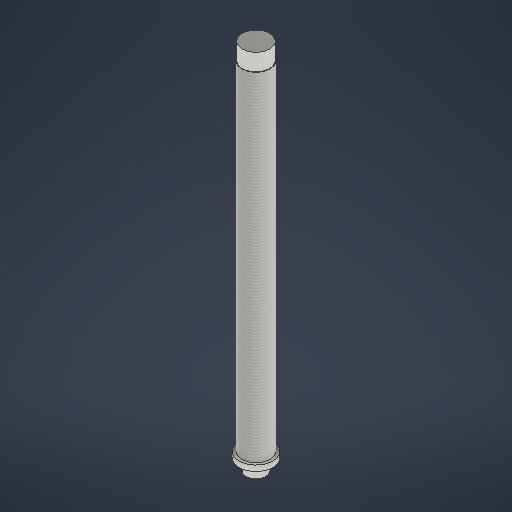
# Autodesk Inventor part: sroba_toczna
Saved by Autodesk Inventor 2027.1 (Build 311270010, 270A)
## iProperties
Created: 2026-11-04
Part Number: sroba_toczna
Material: Ogólny
Document SubType Name: Modeling
Designer: User
Density: 1 g/cm^3
Appearance: Domyślna
Author: User
Autodesk Inventor part; units mm, degrees
ref_plane "YZ Plane" through (0, 0, 0) normal (1, 0, 0) x (0, 1, 0)
ref_plane "XZ Plane" through (0, 0, 0) normal (0, 1, 0) x (-1, 0, 0)
ref_plane "XY Plane" through (0, 0, 0) normal (0, 0, 1) x (1, 0, 0)
sketch "Szkic1" plane through (0, 0, 0) normal (0, 1, 0) x (-1, 0, 0)
  circle A0 centre (0, 0) radius 5
  dimension "d0" = 10
  constraints: 1 centre point, 1 coincident
  measures "d0" diameter of A0
extrude "Wyciągnięcie proste1" add sketch "Szkic1" along normal blind 120
thread "Gwint1" size "M10x1" class "6g" standard "ANSI Metric M Profile" full length
sketch "Szkic2" plane through (0, 120, 0) normal (0, 1, 0) x (1, 0, 0)
  circle A0 centre (0, 0) radius 11.2
  circle A1 centre (0, 0) radius 4.85
  dimension "d5" = 22.4
  dimension "d6" = 9.7
  constraints: 2 centre point, 2 coincident
  measures "d5" diameter of A0
  measures "d6" diameter of A1
extrude "Wyciągnięcie proste2" add sketch "Szkic2" along normal blind 6 contours A1
sketch "Szkic3" plane through (0, 0, 0) normal (0, -1, 0) x (1, 0, 0)
  circle A0 centre (0, 0) radius 3
  line L0 (-2, 1.5) -> (2, 1.5)
  arc A1 (-2, 1.5) -> (-2, -1.5) centre (0, 0) ccw
  line L1 (2, -1.5) -> (-2, -1.5)
  arc A2 (2, -1.5) -> (2, 1.5) centre (0, 0) ccw
  arc A3 (2, 1.5) -> (-2, 1.5) centre (0, 0) ccw
  arc A4 (2, 1.5) -> (-2, 1.5) centre (0, 0) ccw
  line L2 (2, 1.5) -> (-2, 1.5)
  arc A5 (-2, -1.5) -> (2, -1.5) centre (0, 0) ccw
  line L3 (-2, -1.5) -> (2, -1.5)
  circle A6 centre (0, 0) radius 6
  dimension "d9" = 6
  dimension "d14" = 12
  constraints: 10 point on circle, 8 end point, 7 centre point, 2 coincident
  measures "d9" diameter of A0
  measures "d14" diameter of A6
extrude "Wyciągnięcie proste3" add sketch "Szkic3" along normal blind 6 contours A0 | A3 L0 | L1 A5
offset faces "Rozmiar1" outward -0.1 faces at (2.3419, -4, -0.8748) (0.6667, -2, -1.5) (-2.102, -4, 1.3533) (-0.6667, -2, 1.5)
offset faces "Rozmiar2" outward 0.5 faces at (2.9903, -2, 0.2414)
extrude "Wyciągnięcie proste4" add sketch "Szkic3" along normal blind 2 contours A6
